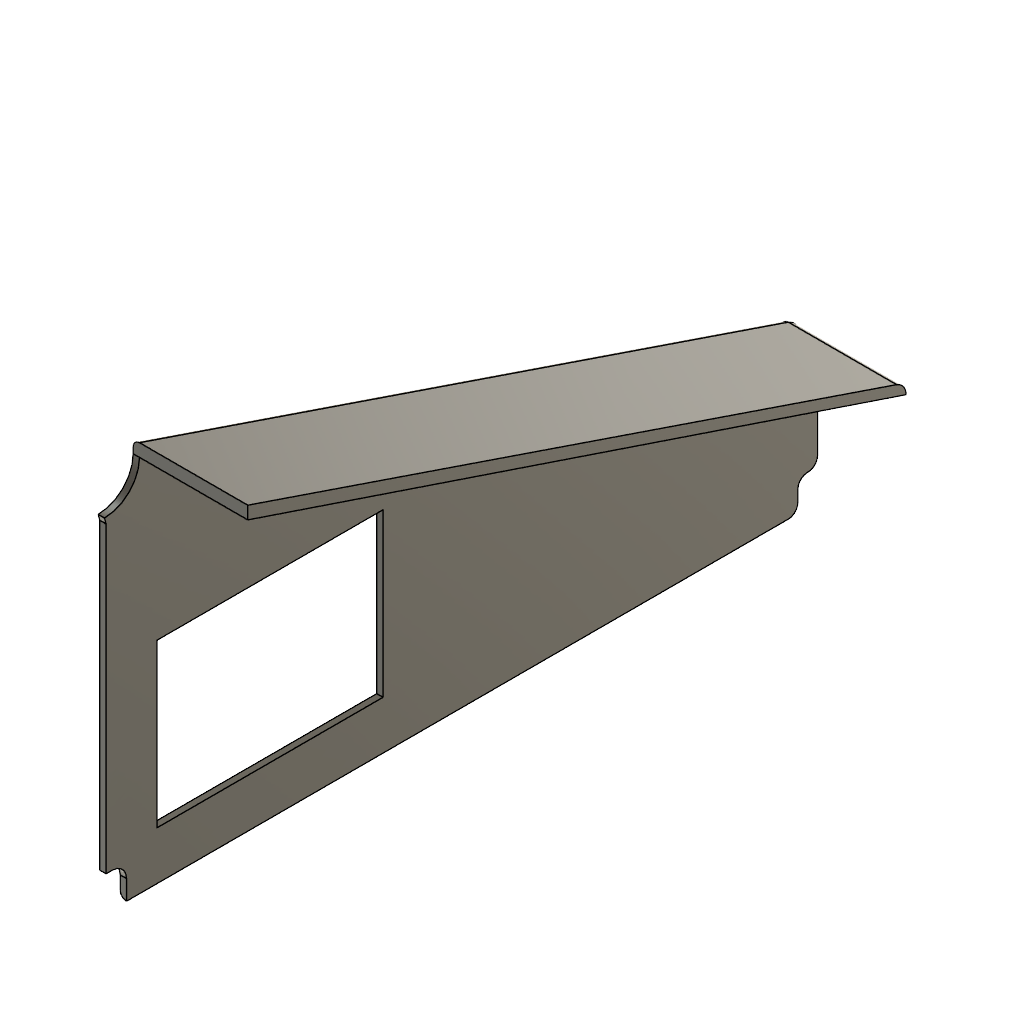
Active-Multifilament-System_v1.1 (Autodesk Fusion 360 archive; units mm, degrees)
design "cover cable"
Autodesk Fusion 360 part; units mm, degrees
sketch "Schizzo1" plane through (0, 0, 0) normal (1, 0, 0) x (0, 1, 0)
  line L0 (-11, 14) -> (-11.1919, 14)
  line L1 (-231.5055, 14.9621) -> (-231.5055, 110.1581)
  line L2 (-24.8589, 4.2999) -> (-225.0738, 4.2999)
  arc A0 (-225.0738, 10.4621) -> (-229.5738, 14.9621) centre (-229.5738, 10.4621) ccw
  line L3 (-229.5738, 14.9621) -> (-231.5055, 14.9621)
  line L4 (-232, 112) -> (-231.5055, 110.1581)
  line L5 (-225.0738, 4.2999) -> (-225.0738, 10.4621)
  arc A1 (-8, 39) -> (-10, 41) centre (-10, 39) ccw
  line L6 (-8, 39) -> (-8, 17)
  arc A2 (-11, 14) -> (-8, 17) centre (-11, 17) ccw
  arc A3 (-14.1607, 53.6356) -> (-17.2156, 57.8972) centre (-18.6607, 53.6356) ccw
  line L7 (-24.7208, 60.4422) -> (-17.2156, 57.8972)
  line L8 (-17.1919, 4.2999) -> (-24.8589, 4.2999)
  arc A4 (-17.1919, 4.2999) -> (-14.1919, 7.2999) centre (-17.1919, 7.2999) ccw
  line L9 (-12.1607, 41) -> (-10, 41)
  line L10 (-14.1607, 53.6356) -> (-14.1607, 43)
  arc A5 (-14.1607, 43) -> (-12.1607, 41) centre (-12.1607, 43) ccw
  line L11 (-14.1919, 11) -> (-14.1919, 7.2999)
  arc A6 (-232, 112) -> (-221, 123) centre (-232, 123) ccw
  line L12 (-221, 127) -> (-24.7208, 60.4422)
  arc A7 (-11.1919, 14) -> (-14.1919, 11) centre (-11.1919, 11) ccw
  line L13 (-14.1607, 53.6356) -> (-221, 123)
  line L14 (-221, 127) -> (-221, 123)
  line L15 (-180, 19.5) -> (-144.5, 19.5)
  line L16 (-180, 19.5) -> (-215.5, 19.5)
  line L17 (-180, 70.5) -> (-144.5, 70.5)
  line L18 (-144.5, 19.5) -> (-144.5, 70.5)
  line L19 (-180, 70.5) -> (-215.5, 70.5)
  line L20 (-215.5, 70.5) -> (-215.5, 19.5)
  dimension "d3" = 11
  dimension "d4" = 4.5
  dimension "d5" = 3
  dimension "d6" = 3
  dimension "d7" = 3
  dimension "d8" = 2
  dimension "d9" = 4.5
  constraint perpendicular L2 L5
  constraint perpendicular L1 L3
  constraint vertical L14
  constraint tangent A6 L14
  constraint coincident L4.start A6.start
  constraint tangent A0 L5
  constraint tangent A0 L3
  constraint parallel L7 L12
  constraint perpendicular L9 L10
  constraint perpendicular L6 L9
  constraint perpendicular L0 L6
  constraint perpendicular L0 L11
  constraint perpendicular L8 L11
  constraint tangent A4 L11
  constraint tangent L8 A4
  constraint tangent L0 A7
  constraint tangent L11 A7
  constraint tangent L0 A2
  constraint tangent L6 A2
  constraint tangent A1 L6
  constraint tangent A1 L9
  constraint tangent L9 A5
  constraint tangent L10 A5
  constraint equal A1 A5
  constraint tangent A3 L10
  constraint tangent A3 L7
  constraint perpendicular L17 L18
  measures "d3" radius of A6
  measures "d4" radius of A0
  measures "d5" radius of A4
  measures "d6" radius of A7
  measures "d7" radius of A2
  measures "d8" radius of A1
  measures "d9" radius of A3
extrude "Estrusione1" add sketch "Schizzo1" against normal blind 2
extrude "Estrusione2" add sketch "Schizzo1" along normal blind 34 contours A3 L7 L12 L13 L14
fillet "Raccordo1" radius 2 13 edges at (-2, -119.1078, 92.4486) (-2, -15.0033, 56.2573) (-2, -14.1607, 48.3178) (-2, -13.5749, 41.5858) (-2, -11.0804, 41) (-2, -8.5858, 40.4142) (-2, -8, 28) (-2, -8.8787, 14.8787) (-2, -11.096, 14) (-2, -13.3132, 13.1213) (-2, -14.1919, 9.15) (-2, -15.0706, 5.1786) (-2, -121.1328, 4.2999)

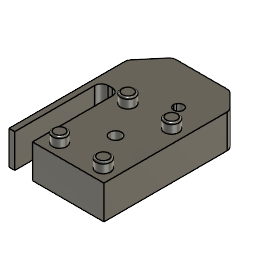
design "Connection"
Autodesk Fusion 360 part; units mm, degrees
sketch "Schizzo1" plane through (0, 0, 0) normal (0, 0, 1) x (1, 0, 0)
  line L0 (51.1687, 18.6809) -> (22.9444, 18.6809)
  circle A0 centre (47.1684, 42.8) radius 3.1356
  line L1 (50.5829, 56.7342) -> (46.6895, 60.6276)
  arc A1 (26.6632, 44.4173) -> (24.6633, 42.4173) centre (26.6632, 42.4173) ccw
  circle A2 centre (42.7913, 49.2634) radius 1.4299
  arc A3 (29.9555, 42.4173) -> (27.9555, 44.4173) centre (27.9555, 42.4173) ccw
  line L2 (24.6633, 18.6809) -> (24.6633, 42.4173)
  circle A4 centre (40.6684, 32.6501) radius 1.75
  arc A5 (46.0406, 61.0612) -> (45.2753, 61.2134) centre (45.5569, 60.6291) ccw
  circle A6 centre (34.1683, 22.5002) radius 3.1356
  circle A7 centre (34.1683, 42.8) radius 3.1356
  circle A8 centre (47.1684, 22.5002) radius 2.1304
  line L3 (26.6632, 44.4173) -> (27.9555, 44.4173)
  spline S0 degree 3 poles (43.4918, 48.0708) (43.462, 48.0499) (43.4312, 48.0303) (43.3997, 48.0121) (43.0008, 47.7818) (42.4742, 47.7726) (42.065, 47.9843) knots 0.128055 0.128055 0.128055 0.128055 0.138564 0.138564 0.138564 0.271538 0.271538 0.271538 0.271538
  line L4 (29.9555, 18.6809) -> (51.1687, 18.6809)
  arc A9 (46.6895, 60.6276) -> (45.2753, 61.2134) centre (45.2753, 59.2134) ccw
  spline S1 degree 3 poles (44.0918, 49.2566) (44.0923, 49.2418) (44.0926, 49.2269) (44.0926, 49.2121) (44.0926, 48.7685) (43.8558, 48.3249) (43.4918, 48.0708) knots 0.827097 0.827097 0.827097 0.827097 0.831382 0.831382 0.831382 0.959437 0.959437 0.959437 0.959437
  spline S2 degree 3 poles (43.4545, 50.3786) (43.8272, 50.1374) (44.0761, 49.7002) (44.0918, 49.2566) knots 0.698987 0.698987 0.698987 0.698987 0.827097 0.827097 0.827097 0.827097
  spline S3 degree 3 poles (41.3223, 49.2634) (41.3412, 49.726) (41.6347, 50.2165) (42.078, 50.4472) (42.111, 50.4626) knots 0.420617 0.420617 0.420617 0.420617 0.554255 0.564763 0.564763 0.564763 0.564763
  spline S4 degree 3 poles (42.111, 50.4626) (42.5131, 50.6508) (43.0398, 50.6331) (43.4365, 50.3903) (43.4545, 50.3786) knots 0.564763 0.564763 0.564763 0.564763 0.692805 0.698987 0.698987 0.698987 0.698987
  arc A10 (51.1687, 55.32) -> (50.5829, 56.7342) centre (49.1688, 55.32) ccw
  arc A11 (30.0518, 61.2134) -> (28.6376, 60.6277) centre (30.0518, 59.2135) ccw
  line L5 (29.9555, 42.4173) -> (29.9555, 18.6809)
  spline S5 degree 3 poles (42.065, 47.9843) (42.0479, 47.9932) (42.0309, 48.0025) (42.0142, 48.0121) (41.5985, 48.2521) (41.3114, 48.7492) (41.3216, 49.2463) (41.3223, 49.2634) knots 0.271538 0.271538 0.271538 0.271538 0.277114 0.277114 0.277114 0.415678 0.420617 0.420617 0.420617 0.420617
  line L6 (51.1687, 18.6809) -> (51.1687, 55.32)
  line L7 (22.9444, 53.1099) -> (22.9444, 18.6809)
  line L8 (22.9444, 18.6809) -> (51.1687, 18.6809)
  line L9 (45.2753, 61.2134) -> (30.0518, 61.2134)
  line L10 (22.9444, 18.6809) -> (24.6633, 18.6809)
  circle A12 centre (34.1683, 22.5002) radius 2.07
  line L11 (51.1687, 18.6809) -> (51.1687, 55.32)
  circle A13 centre (40.6684, 32.6501) radius 1.75
  circle A14 centre (34.1683, 42.8) radius 2.1264
  line L12 (28.6376, 60.6277) -> (23.4118, 54.3949)
  circle A15 centre (47.1684, 42.8) radius 2.1203
  circle A16 centre (47.1684, 22.5002) radius 3.1356
  line L13 (29.9555, 18.6809) -> (24.6633, 18.6809)
  arc A17 (23.4118, 54.3949) -> (22.9444, 53.1099) centre (24.9444, 53.1099) ccw
  dimension "d6" = 2
  constraint horizontal L8
  constraint vertical L11
  constraint coincident L0.end L7.end
  constraint coincident A10.start L6.end
  constraint horizontal L0
  constraint concentric A7 A14
  constraint concentric A0 A15
  constraint concentric A8 A16
  constraint concentric A6 A12
  constraint concentric A4 A13
  constraint horizontal L13
  constraint coincident L4.start L5.end
  constraint midpoint A5.start A9
  constraint coincident A5.end A9.end
  constraint vertical L7
  constraint tangent L12 A17
  constraint tangent L7 A17
  measures "d6" radius of A17
extrude "Estrusione1" add sketch "Schizzo1" along normal blind 3 contours A8 | A12 | A14 | A15 makes body 1 at (49.2861, 42.6943, 2) makes body 2 at (49.2961, 22.394, 2) makes body 3 at (36.292, 42.694, 2) makes body 4 at (36.2357, 22.3971, 2)
extrude "Estrusione2" add sketch "Schizzo1" against normal blind 10 contours L0 L1 A1 A3 L2 L3 L4 A9 A10 A11 L5 L6 L7 L8 L9 L10 L11 L12 A17 | A0 | A6 | A7 | A8 | A12 | A14 | A15 | A16 bodies 1 2 3 4
fillet "Raccordo1" radius 0.5 1 edges at (45.1916, 42.0332, 3) on bodies 1
fillet "Raccordo2" radius 0.5 3 edges at (45.1822, 21.7299, 3) (32.2384, 21.7517, 3) (32.1859, 42.031, 3) on bodies 1 2 3 4
sketch "Schizzo2" plane through (0, 0, -10) normal (0, 0, -1) x (1, 0, 0)
  line L0 (29.9555, -18.6809) -> (29.9555, -42.4173)
  arc A0 (27.9555, -44.4173) -> (29.9555, -42.4173) centre (27.9555, -42.4173) ccw
  line L1 (27.9555, -44.4173) -> (26.6632, -44.4173)
  arc A1 (24.6633, -42.4173) -> (26.6632, -44.4173) centre (26.6632, -42.4173) ccw
  line L2 (24.6633, -42.4173) -> (24.6633, -18.6809)
  line L3 (24.6633, -18.6809) -> (22.9444, -18.6809)
  line L4 (22.9444, -18.6809) -> (22.9444, -53.1099)
  arc A2 (22.9444, -53.1099) -> (23.4118, -54.3949) centre (24.9444, -53.1099) ccw
  line L5 (23.4118, -54.3949) -> (28.6376, -60.6277)
  arc A3 (28.6376, -60.6277) -> (30.0518, -61.2134) centre (30.0518, -59.2135) ccw
  line L6 (30.0518, -61.2134) -> (45.2753, -61.2134)
  arc A4 (45.2753, -61.2134) -> (46.6895, -60.6276) centre (45.2753, -59.2134) ccw
  line L7 (46.6895, -60.6276) -> (50.5829, -56.7342)
  arc A5 (50.5829, -56.7342) -> (51.1687, -55.32) centre (49.1688, -55.32) ccw
  line L8 (51.1687, -55.32) -> (51.1687, -18.6809)
  line L9 (51.1687, -18.6809) -> (29.9555, -18.6809)
  spline S0 degree 3 poles (42.065, -47.9843) (42.2804, -47.8729) (42.5284, -47.8226) (42.7731, -47.8336) knots -0.271538 -0.271538 -0.271538 -0.271538 -0.20154 -0.20154 -0.20154 -0.20154
  arc A6 (41.5135, -49.9051) -> (42.7731, -47.8336) centre (42.7913, -49.2634) ccw
  spline S1 degree 3 poles (41.5135, -49.9051) (41.3999, -49.7093) (41.3315, -49.4873) (41.3223, -49.2634) knots -0.48529 -0.48529 -0.48529 -0.48529 -0.420617 -0.420617 -0.420617 -0.420617
  spline S2 degree 3 poles (41.3223, -49.2634) (41.3216, -49.2463) (41.3114, -48.7492) (41.5985, -48.2521) (42.0142, -48.0121) (42.0309, -48.0025) (42.0479, -47.9932) (42.065, -47.9843) knots -0.420617 -0.420617 -0.420617 -0.420617 -0.415678 -0.277114 -0.277114 -0.277114 -0.271538 -0.271538 -0.271538 -0.271538
  circle A7 centre (40.6684, -32.6501) radius 1.75
  circle A8 centre (40.6684, -32.6501) radius 3.2
  dimension "d11" = 6.4
  constraint concentric A7 A8
  measures "d11" diameter of A8
extrude "Estrusione3" cut sketch "Schizzo2" against normal blind 5 contours A8 bodies 1
sketch "Schizzo3" plane through (51.1687, 0, 0) normal (1, 0, 0) x (0, 1, 0)
  line L0 (55.32, 0) -> (18.6809, 0)
  line L1 (18.6809, 0) -> (18.6809, -10)
  line L2 (18.6809, -10) -> (55.32, -10)
  line L3 (55.32, -10) -> (55.32, 0)
  line L4 (20.8044, -13.8) -> (48.028, -13.7999)
  line L5 (48.0078, -6.2374) -> (44.6936, -6.2373)
  line L6 (48.028, -13.7999) -> (48.0078, -6.2374)
  line L7 (59.0432, -9.8918) -> (24.3129, -23.9317)
  line L8 (24.3129, -23.9317) -> (18.6809, -10)
  line L9 (18.6809, -10) -> (59.0432, -9.8918)
  point P0 (23.5262, -10.543)
  point P1 (23.526, -10.5432)
  point P2 (19.4334, -17.9328)
  point P3 (44.6936, -6.2373)
  constraint perpendicular L7 L8
  constraint perpendicular L6 L9
  constraint coincident L1.end L2.start
sketch "Schizzo4" plane through (0, 0, -10) normal (0, 0, -1) x (1, 0, 0)
  circle A0 centre (40.6684, -32.6501) radius 3.2
  arc A1 (41.5135, -49.9051) -> (42.7731, -47.8336) centre (42.7913, -49.2634) ccw
  spline S0 degree 3 poles (41.5135, -49.9051) (41.3999, -49.7093) (41.3315, -49.4873) (41.3223, -49.2634) knots -0.48529 -0.48529 -0.48529 -0.48529 -0.420617 -0.420617 -0.420617 -0.420617
  spline S1 degree 3 poles (41.3223, -49.2634) (41.3216, -49.2463) (41.3114, -48.7492) (41.5985, -48.2521) (42.0142, -48.0121) (42.0309, -48.0025) (42.0479, -47.9932) (42.065, -47.9843) knots -0.420617 -0.420617 -0.420617 -0.420617 -0.415678 -0.277114 -0.277114 -0.277114 -0.271538 -0.271538 -0.271538 -0.271538
  spline S2 degree 3 poles (42.065, -47.9843) (42.2804, -47.8729) (42.5284, -47.8226) (42.7731, -47.8336) knots -0.271538 -0.271538 -0.271538 -0.271538 -0.20154 -0.20154 -0.20154 -0.20154
  line L0 (29.9555, -18.6809) -> (29.9555, -42.4173)
  arc A2 (27.9555, -44.4173) -> (29.9555, -42.4173) centre (27.9555, -42.4173) ccw
  line L1 (27.9555, -44.4173) -> (26.6632, -44.4173)
  arc A3 (24.6633, -42.4173) -> (26.6632, -44.4173) centre (26.6632, -42.4173) ccw
  line L2 (24.6633, -42.4173) -> (24.6633, -18.6809)
  line L3 (24.6633, -18.6809) -> (22.9444, -18.6809)
  line L4 (22.9444, -18.6809) -> (22.9444, -53.1099)
  arc A4 (22.9444, -53.1099) -> (23.4118, -54.3949) centre (24.9444, -53.1099) ccw
  line L5 (23.4118, -54.3949) -> (28.6376, -60.6277)
  arc A5 (28.6376, -60.6277) -> (30.0518, -61.2134) centre (30.0518, -59.2135) ccw
  line L6 (30.0518, -61.2134) -> (45.2753, -61.2134)
  arc A6 (45.2753, -61.2134) -> (46.6895, -60.6276) centre (45.2753, -59.2134) ccw
  line L7 (46.6895, -60.6276) -> (50.5829, -56.7342)
  arc A7 (50.5829, -56.7342) -> (51.1687, -55.32) centre (49.1688, -55.32) ccw
  line L8 (51.1687, -55.32) -> (51.1687, -18.6809)
  line L9 (51.1687, -18.6809) -> (29.9555, -18.6809)
  circle A8 centre (42.7913, -49.2634) radius 4.175
  dimension "d14" = 8.35
  constraint concentric A1 A8
  measures "d14" diameter of A8
extrude "Estrusione4" cut sketch "Schizzo4" against normal blind 8 contours A8 bodies 1
chamfer "Smusso1" distance 0.5 angle 45 1 edges at (38.8989, 47.7537, -10) on bodies 1
fillet "Raccordo3" radius 2 1 edges at (38.8989, 47.7537, -2) on bodies 1
